Autodesk Fusion 360 part; units mm, degrees
(part 2 of 3)
sketch "24 tooth involute gear profile (2)" plane through (0, 0, 3) normal (0, 0, 1) x (1, 0, 0) in component "Right 24T gear and crank"
  line L0 (25.5783, 0.611) -> (26.1696, 0.6409)
  line L1 (26.1696, 0.6409) -> (26.4898, 0.7065)
  line L2 (26.4898, 0.7065) -> (26.8073, 0.8147)
  line L3 (26.8073, 0.8147) -> (27.1222, 0.9526)
  line L4 (27.1222, 0.9526) -> (27.434, 1.1157)
  line L5 (27.434, 1.1157) -> (27.7424, 1.3018)
  line L6 (27.7424, 1.3018) -> (28.0469, 1.5092)
  line L7 (28.0469, 1.5092) -> (27.9419, 2.3072)
  line L8 (27.9419, 2.3072) -> (27.5941, 2.4288)
  line L9 (27.5941, 2.4288) -> (27.248, 2.5287)
  line L10 (27.248, 2.5287) -> (26.9045, 2.6055)
  line L11 (26.9045, 2.6055) -> (26.5648, 2.6572)
  line L12 (26.5648, 2.6572) -> (26.2301, 2.6796)
  line L13 (26.2301, 2.6796) -> (25.9038, 2.66)
  line L14 (25.9038, 2.66) -> (25.3249, 2.5359)
  line L15 (25.3249, 2.5359) -> (25.0086, 3.7163)
  line L16 (25.0086, 3.7163) -> (25.5721, 3.8982)
  line L17 (25.5721, 3.8982) -> (25.8644, 4.0445)
  line L18 (25.8644, 4.0445) -> (26.143, 4.2312)
  line L19 (26.143, 4.2312) -> (26.4114, 4.4458)
  line L20 (26.4114, 4.4458) -> (26.6705, 4.6841)
  line L21 (26.6705, 4.6841) -> (26.9202, 4.9436)
  line L22 (26.9202, 4.9436) -> (27.1606, 5.2228)
  line L23 (27.1606, 5.2228) -> (26.8526, 5.9664)
  line L24 (26.8526, 5.9664) -> (26.4852, 5.9939)
  line L25 (26.4852, 5.9939) -> (26.1251, 6.0008)
  line L26 (26.1251, 6.0008) -> (25.7734, 5.9861)
  line L27 (25.7734, 5.9861) -> (25.4318, 5.9481)
  line L28 (25.4318, 5.9481) -> (25.1028, 5.8831)
  line L29 (25.1028, 5.8831) -> (24.7927, 5.7798)
  line L30 (24.7927, 5.7798) -> (24.2656, 5.51)
  line L31 (24.2656, 5.51) -> (23.6546, 6.5683)
  line L32 (23.6546, 6.5683) -> (24.1518, 6.8899)
  line L33 (24.1518, 6.8899) -> (24.3963, 7.1068)
  line L34 (24.3963, 7.1068) -> (24.6171, 7.3592)
  line L35 (24.6171, 7.3592) -> (24.8208, 7.636)
  line L36 (24.8208, 7.636) -> (25.0094, 7.9332)
  line L37 (25.0094, 7.9332) -> (25.1834, 8.2486)
  line L38 (25.1834, 8.2486) -> (25.3434, 8.5805)
  line L39 (25.3434, 8.5805) -> (24.8534, 9.219)
  line L40 (24.8534, 9.219) -> (24.4914, 9.1504)
  line L41 (24.4914, 9.1504) -> (24.1418, 9.0639)
  line L42 (24.1418, 9.0639) -> (23.8059, 8.9587)
  line L43 (23.8059, 8.9587) -> (23.4858, 8.8336)
  line L44 (23.4858, 8.8336) -> (23.1848, 8.6856)
  line L45 (23.1848, 8.6856) -> (22.912, 8.5056)
  line L46 (22.912, 8.5056) -> (22.4727, 8.1086)
  line L47 (22.4727, 8.1086) -> (21.6086, 8.9727)
  line L48 (21.6086, 8.9727) -> (22.0056, 9.412)
  line L49 (22.0056, 9.412) -> (22.1856, 9.6848)
  line L50 (22.1856, 9.6848) -> (22.3336, 9.9858)
  line L51 (22.3336, 9.9858) -> (22.4587, 10.3059)
  line L52 (22.4587, 10.3059) -> (22.5639, 10.6418)
  line L53 (22.5639, 10.6418) -> (22.6504, 10.9914)
  line L54 (22.6504, 10.9914) -> (22.719, 11.3534)
  line L55 (22.719, 11.3534) -> (22.0805, 11.8434)
  line L56 (22.0805, 11.8434) -> (21.7486, 11.6834)
  line L57 (21.7486, 11.6834) -> (21.4332, 11.5094)
  line L58 (21.4332, 11.5094) -> (21.136, 11.3208)
  line L59 (21.136, 11.3208) -> (20.8592, 11.1171)
  line L60 (20.8592, 11.1171) -> (20.6068, 10.8963)
  line L61 (20.6068, 10.8963) -> (20.3899, 10.6518)
  line L62 (20.3899, 10.6518) -> (20.0683, 10.1546)
  line L63 (20.0683, 10.1546) -> (19.01, 10.7656)
  line L64 (19.01, 10.7656) -> (19.2798, 11.2927)
  line L65 (19.2798, 11.2927) -> (19.3831, 11.6028)
  line L66 (19.3831, 11.6028) -> (19.4481, 11.9318)
  line L67 (19.4481, 11.9318) -> (19.4861, 12.2734)
  line L68 (19.4861, 12.2734) -> (19.5008, 12.6251)
  line L69 (19.5008, 12.6251) -> (19.4939, 12.9852)
  line L70 (19.4939, 12.9852) -> (19.4664, 13.3526)
  line L71 (19.4664, 13.3526) -> (18.7228, 13.6606)
  line L72 (18.7228, 13.6606) -> (18.4436, 13.4202)
  line L73 (18.4436, 13.4202) -> (18.1841, 13.1705)
  line L74 (18.1841, 13.1705) -> (17.9458, 12.9114)
  line L75 (17.9458, 12.9114) -> (17.7312, 12.643)
  line L76 (17.7312, 12.643) -> (17.5445, 12.3644)
  line L77 (17.5445, 12.3644) -> (17.3982, 12.0721)
  line L78 (17.3982, 12.0721) -> (17.2163, 11.5086)
  line L79 (17.2163, 11.5086) -> (16.0359, 11.8249)
  line L80 (16.0359, 11.8249) -> (16.16, 12.4038)
  line L81 (16.16, 12.4038) -> (16.1796, 12.7301)
  line L82 (16.1796, 12.7301) -> (16.1572, 13.0648)
  line L83 (16.1572, 13.0648) -> (16.1055, 13.4045)
  line L84 (16.1055, 13.4045) -> (16.0287, 13.748)
  line L85 (16.0287, 13.748) -> (15.9288, 14.0941)
  line L86 (15.9288, 14.0941) -> (15.8072, 14.4419)
  line L87 (15.8072, 14.4419) -> (15.0092, 14.5469)
  line L88 (15.0092, 14.5469) -> (14.8018, 14.2424)
  line L89 (14.8018, 14.2424) -> (14.6157, 13.934)
  line L90 (14.6157, 13.934) -> (14.4526, 13.6222)
  line L91 (14.4526, 13.6222) -> (14.3147, 13.3073)
  line L92 (14.3147, 13.3073) -> (14.2065, 12.9898)
  line L93 (14.2065, 12.9898) -> (14.1409, 12.6696)
  line L94 (14.1409, 12.6696) -> (14.111, 12.0783)
  line L95 (14.111, 12.0783) -> (12.889, 12.0783)
  line L96 (12.889, 12.0783) -> (12.8591, 12.6696)
  line L97 (12.8591, 12.6696) -> (12.7935, 12.9898)
  line L98 (12.7935, 12.9898) -> (12.6853, 13.3073)
  line L99 (12.6853, 13.3073) -> (12.5474, 13.6222)
  line L100 (12.5474, 13.6222) -> (12.3843, 13.934)
  line L101 (12.3843, 13.934) -> (12.1982, 14.2424)
  line L102 (12.1982, 14.2424) -> (11.9908, 14.5469)
  line L103 (11.9908, 14.5469) -> (11.1928, 14.4419)
  line L104 (11.1928, 14.4419) -> (11.0712, 14.0941)
  line L105 (11.0712, 14.0941) -> (10.9713, 13.748)
  line L106 (10.9713, 13.748) -> (10.8945, 13.4045)
  line L107 (10.8945, 13.4045) -> (10.8428, 13.0648)
  line L108 (10.8428, 13.0648) -> (10.8204, 12.7301)
  line L109 (10.8204, 12.7301) -> (10.84, 12.4038)
  line L110 (10.84, 12.4038) -> (10.9641, 11.8249)
  line L111 (10.9641, 11.8249) -> (9.7837, 11.5086)
  line L112 (9.7837, 11.5086) -> (9.6018, 12.0721)
  line L113 (9.6018, 12.0721) -> (9.4555, 12.3644)
  line L114 (9.4555, 12.3644) -> (9.2688, 12.643)
  line L115 (9.2688, 12.643) -> (9.0542, 12.9114)
  line L116 (9.0542, 12.9114) -> (8.8159, 13.1705)
  line L117 (8.8159, 13.1705) -> (8.5564, 13.4202)
  line L118 (8.5564, 13.4202) -> (8.2772, 13.6606)
  line L119 (8.2772, 13.6606) -> (7.5336, 13.3526)
  line L120 (7.5336, 13.3526) -> (7.5061, 12.9852)
  line L121 (7.5061, 12.9852) -> (7.4992, 12.6251)
  line L122 (7.4992, 12.6251) -> (7.5139, 12.2734)
  line L123 (7.5139, 12.2734) -> (7.5519, 11.9318)
  line L124 (7.5519, 11.9318) -> (7.6169, 11.6028)
  line L125 (7.6169, 11.6028) -> (7.7202, 11.2927)
  line L126 (7.7202, 11.2927) -> (7.99, 10.7656)
  line L127 (7.99, 10.7656) -> (6.9317, 10.1546)
  line L128 (6.9317, 10.1546) -> (6.6101, 10.6518)
  line L129 (6.6101, 10.6518) -> (6.3932, 10.8963)
  line L130 (6.3932, 10.8963) -> (6.1408, 11.1171)
  line L131 (6.1408, 11.1171) -> (5.864, 11.3208)
  line L132 (5.864, 11.3208) -> (5.5668, 11.5094)
  line L133 (5.5668, 11.5094) -> (5.2514, 11.6834)
  line L134 (5.2514, 11.6834) -> (4.9195, 11.8434)
  line L135 (4.9195, 11.8434) -> (4.281, 11.3534)
  line L136 (4.281, 11.3534) -> (4.3496, 10.9914)
  line L137 (4.3496, 10.9914) -> (4.4361, 10.6418)
  line L138 (4.4361, 10.6418) -> (4.5413, 10.3059)
  line L139 (4.5413, 10.3059) -> (4.6664, 9.9858)
  line L140 (4.6664, 9.9858) -> (4.8144, 9.6848)
  line L141 (4.8144, 9.6848) -> (4.9944, 9.412)
  line L142 (4.9944, 9.412) -> (5.3914, 8.9727)
  line L143 (5.3914, 8.9727) -> (4.5273, 8.1086)
  line L144 (4.5273, 8.1086) -> (4.088, 8.5056)
  line L145 (4.088, 8.5056) -> (3.8152, 8.6856)
  line L146 (3.8152, 8.6856) -> (3.5142, 8.8336)
  line L147 (3.5142, 8.8336) -> (3.1941, 8.9587)
  line L148 (3.1941, 8.9587) -> (2.8582, 9.0639)
  line L149 (2.8582, 9.0639) -> (2.5086, 9.1504)
  line L150 (2.5086, 9.1504) -> (2.1466, 9.219)
  line L151 (2.1466, 9.219) -> (1.6566, 8.5805)
  line L152 (1.6566, 8.5805) -> (1.8166, 8.2486)
  line L153 (1.8166, 8.2486) -> (1.9906, 7.9332)
  line L154 (1.9906, 7.9332) -> (2.1792, 7.636)
  line L155 (2.1792, 7.636) -> (2.3829, 7.3592)
  line L156 (2.3829, 7.3592) -> (2.6037, 7.1068)
  line L157 (2.6037, 7.1068) -> (2.8482, 6.8899)
  line L158 (2.8482, 6.8899) -> (3.3454, 6.5683)
  line L159 (3.3454, 6.5683) -> (2.7344, 5.51)
  line L160 (2.7344, 5.51) -> (2.2073, 5.7798)
  line L161 (2.2073, 5.7798) -> (1.8972, 5.8831)
  line L162 (1.8972, 5.8831) -> (1.5682, 5.9481)
  line L163 (1.5682, 5.9481) -> (1.2266, 5.9861)
  line L164 (1.2266, 5.9861) -> (0.8749, 6.0008)
  line L165 (0.8749, 6.0008) -> (0.5148, 5.9939)
  line L166 (0.5148, 5.9939) -> (0.1474, 5.9664)
  line L167 (0.1474, 5.9664) -> (-0.1606, 5.2228)
  line L168 (-0.1606, 5.2228) -> (0.0798, 4.9436)
  line L169 (0.0798, 4.9436) -> (0.3295, 4.6841)
  line L170 (0.3295, 4.6841) -> (0.5886, 4.4458)
  line L171 (0.5886, 4.4458) -> (0.857, 4.2312)
  line L172 (0.857, 4.2312) -> (1.1356, 4.0445)
  line L173 (1.1356, 4.0445) -> (1.4279, 3.8982)
  line L174 (1.4279, 3.8982) -> (1.9914, 3.7163)
  line L175 (1.9914, 3.7163) -> (1.6751, 2.5359)
  line L176 (1.6751, 2.5359) -> (1.0962, 2.66)
  line L177 (1.0962, 2.66) -> (0.7699, 2.6796)
  line L178 (0.7699, 2.6796) -> (0.4352, 2.6572)
  line L179 (0.4352, 2.6572) -> (0.0955, 2.6055)
  line L180 (0.0955, 2.6055) -> (-0.248, 2.5287)
  line L181 (-0.248, 2.5287) -> (-0.5941, 2.4288)
  line L182 (-0.5941, 2.4288) -> (-0.9419, 2.3072)
  line L183 (-0.9419, 2.3072) -> (-1.0469, 1.5092)
  line L184 (-1.0469, 1.5092) -> (-0.7424, 1.3018)
  line L185 (-0.7424, 1.3018) -> (-0.434, 1.1157)
  line L186 (-0.434, 1.1157) -> (-0.1222, 0.9526)
  line L187 (-0.1222, 0.9526) -> (0.1927, 0.8147)
  line L188 (0.1927, 0.8147) -> (0.5102, 0.7065)
  line L189 (0.5102, 0.7065) -> (0.8304, 0.6409)
  line L190 (0.8304, 0.6409) -> (1.4217, 0.611)
  line L191 (1.4217, 0.611) -> (1.4217, -0.611)
  line L192 (1.4217, -0.611) -> (0.8304, -0.6409)
  line L193 (0.8304, -0.6409) -> (0.5102, -0.7065)
  line L194 (0.5102, -0.7065) -> (0.1927, -0.8147)
  line L195 (0.1927, -0.8147) -> (-0.1222, -0.9526)
  line L196 (-0.1222, -0.9526) -> (-0.434, -1.1157)
  line L197 (-0.434, -1.1157) -> (-0.7424, -1.3018)
  line L198 (-0.7424, -1.3018) -> (-1.0469, -1.5092)
  line L199 (-1.0469, -1.5092) -> (-0.9419, -2.3072)
  line L200 (-0.9419, -2.3072) -> (-0.5941, -2.4288)
  line L201 (-0.5941, -2.4288) -> (-0.248, -2.5287)
  line L202 (-0.248, -2.5287) -> (0.0955, -2.6055)
  line L203 (0.0955, -2.6055) -> (0.4352, -2.6572)
  line L204 (0.4352, -2.6572) -> (0.7699, -2.6796)
  line L205 (0.7699, -2.6796) -> (1.0962, -2.66)
  line L206 (1.0962, -2.66) -> (1.6751, -2.5359)
  line L207 (1.6751, -2.5359) -> (1.9914, -3.7163)
  line L208 (1.9914, -3.7163) -> (1.4279, -3.8982)
  line L209 (1.4279, -3.8982) -> (1.1356, -4.0445)
  line L210 (1.1356, -4.0445) -> (0.857, -4.2312)
  line L211 (0.857, -4.2312) -> (0.5886, -4.4458)
  line L212 (0.5886, -4.4458) -> (0.3295, -4.6841)
  line L213 (0.3295, -4.6841) -> (0.0798, -4.9436)
  line L214 (0.0798, -4.9436) -> (-0.1606, -5.2228)
  line L215 (-0.1606, -5.2228) -> (0.1474, -5.9664)
  line L216 (0.1474, -5.9664) -> (0.5148, -5.9939)
  line L217 (0.5148, -5.9939) -> (0.8749, -6.0008)
  line L218 (0.8749, -6.0008) -> (1.2266, -5.9861)
  line L219 (1.2266, -5.9861) -> (1.5682, -5.9481)
  line L220 (1.5682, -5.9481) -> (1.8972, -5.8831)
  line L221 (1.8972, -5.8831) -> (2.2073, -5.7798)
  line L222 (2.2073, -5.7798) -> (2.7344, -5.51)
  line L223 (2.7344, -5.51) -> (3.3454, -6.5683)
  line L224 (3.3454, -6.5683) -> (2.8482, -6.8899)
  line L225 (2.8482, -6.8899) -> (2.6037, -7.1068)
  line L226 (2.6037, -7.1068) -> (2.3829, -7.3592)
  line L227 (2.3829, -7.3592) -> (2.1792, -7.636)
  line L228 (2.1792, -7.636) -> (1.9906, -7.9332)
  line L229 (1.9906, -7.9332) -> (1.8166, -8.2486)
  line L230 (1.8166, -8.2486) -> (1.6566, -8.5805)
  line L231 (1.6566, -8.5805) -> (2.1466, -9.219)
  line L232 (2.1466, -9.219) -> (2.5086, -9.1504)
  line L233 (2.5086, -9.1504) -> (2.8582, -9.0639)
  line L234 (2.8582, -9.0639) -> (3.1941, -8.9587)
  line L235 (3.1941, -8.9587) -> (3.5142, -8.8336)
  line L236 (3.5142, -8.8336) -> (3.8152, -8.6856)
  line L237 (3.8152, -8.6856) -> (4.088, -8.5056)
  line L238 (4.088, -8.5056) -> (4.5273, -8.1086)
  line L239 (4.5273, -8.1086) -> (5.3914, -8.9727)
  line L240 (5.3914, -8.9727) -> (4.9944, -9.412)
  line L241 (4.9944, -9.412) -> (4.8144, -9.6848)
  line L242 (4.8144, -9.6848) -> (4.6664, -9.9858)
  line L243 (4.6664, -9.9858) -> (4.5413, -10.3059)
  line L244 (4.5413, -10.3059) -> (4.4361, -10.6418)
  line L245 (4.4361, -10.6418) -> (4.3496, -10.9914)
  line L246 (4.3496, -10.9914) -> (4.281, -11.3534)
  line L247 (4.281, -11.3534) -> (4.9195, -11.8434)
  line L248 (4.9195, -11.8434) -> (5.2514, -11.6834)
  line L249 (5.2514, -11.6834) -> (5.5668, -11.5094)
  line L250 (5.5668, -11.5094) -> (5.864, -11.3208)
  line L251 (5.864, -11.3208) -> (6.1408, -11.1171)
  line L252 (6.1408, -11.1171) -> (6.3932, -10.8963)
  line L253 (6.3932, -10.8963) -> (6.6101, -10.6518)
  line L254 (6.6101, -10.6518) -> (6.9317, -10.1546)
  line L255 (6.9317, -10.1546) -> (7.99, -10.7656)
  line L256 (7.99, -10.7656) -> (7.7202, -11.2927)
  line L257 (7.7202, -11.2927) -> (7.6169, -11.6028)
  line L258 (7.6169, -11.6028) -> (7.5519, -11.9318)
  line L259 (7.5519, -11.9318) -> (7.5139, -12.2734)
  line L260 (7.5139, -12.2734) -> (7.4992, -12.6251)
  line L261 (7.4992, -12.6251) -> (7.5061, -12.9852)
  line L262 (7.5061, -12.9852) -> (7.5336, -13.3526)
  line L263 (7.5336, -13.3526) -> (8.2772, -13.6606)
  line L264 (8.2772, -13.6606) -> (8.5564, -13.4202)
  line L265 (8.5564, -13.4202) -> (8.8159, -13.1705)
  line L266 (8.8159, -13.1705) -> (9.0542, -12.9114)
  line L267 (9.0542, -12.9114) -> (9.2688, -12.643)
  line L268 (9.2688, -12.643) -> (9.4555, -12.3644)
  line L269 (9.4555, -12.3644) -> (9.6018, -12.0721)
  line L270 (9.6018, -12.0721) -> (9.7837, -11.5086)
  line L271 (9.7837, -11.5086) -> (10.9641, -11.8249)
  line L272 (10.9641, -11.8249) -> (10.84, -12.4038)
  line L273 (10.84, -12.4038) -> (10.8204, -12.7301)
  line L274 (10.8204, -12.7301) -> (10.8428, -13.0648)
  line L275 (10.8428, -13.0648) -> (10.8945, -13.4045)
  line L276 (10.8945, -13.4045) -> (10.9713, -13.748)
  line L277 (10.9713, -13.748) -> (11.0712, -14.0941)
  line L278 (11.0712, -14.0941) -> (11.1928, -14.4419)
  line L279 (11.1928, -14.4419) -> (11.9908, -14.5469)
  line L280 (11.9908, -14.5469) -> (12.1982, -14.2424)
  line L281 (12.1982, -14.2424) -> (12.3843, -13.934)
  line L282 (12.3843, -13.934) -> (12.5474, -13.6222)
  line L283 (12.5474, -13.6222) -> (12.6853, -13.3073)
  line L284 (12.6853, -13.3073) -> (12.7935, -12.9898)
  line L285 (12.7935, -12.9898) -> (12.8591, -12.6696)
  line L286 (12.8591, -12.6696) -> (12.889, -12.0783)
  line L287 (12.889, -12.0783) -> (14.111, -12.0783)
  line L288 (14.111, -12.0783) -> (14.1409, -12.6696)
  line L289 (14.1409, -12.6696) -> (14.2065, -12.9898)
  line L290 (14.2065, -12.9898) -> (14.3147, -13.3073)
  line L291 (14.3147, -13.3073) -> (14.4526, -13.6222)
  line L292 (14.4526, -13.6222) -> (14.6157, -13.934)
  line L293 (14.6157, -13.934) -> (14.8018, -14.2424)
  line L294 (14.8018, -14.2424) -> (15.0092, -14.5469)
  line L295 (15.0092, -14.5469) -> (15.8072, -14.4419)
  line L296 (15.8072, -14.4419) -> (15.9288, -14.0941)
  line L297 (15.9288, -14.0941) -> (16.0287, -13.748)
  line L298 (16.0287, -13.748) -> (16.1055, -13.4045)
  line L299 (16.1055, -13.4045) -> (16.1572, -13.0648)
  line L300 (16.1572, -13.0648) -> (16.1796, -12.7301)
  line L301 (16.1796, -12.7301) -> (16.16, -12.4038)
  line L302 (16.16, -12.4038) -> (16.0359, -11.8249)
  line L303 (16.0359, -11.8249) -> (17.2163, -11.5086)
  line L304 (17.2163, -11.5086) -> (17.3982, -12.0721)
  line L305 (17.3982, -12.0721) -> (17.5445, -12.3644)
  line L306 (17.5445, -12.3644) -> (17.7312, -12.643)
  line L307 (17.7312, -12.643) -> (17.9458, -12.9114)
  line L308 (17.9458, -12.9114) -> (18.1841, -13.1705)
  line L309 (18.1841, -13.1705) -> (18.4436, -13.4202)
  line L310 (18.4436, -13.4202) -> (18.7228, -13.6606)
  line L311 (18.7228, -13.6606) -> (19.4664, -13.3526)
  line L312 (19.4664, -13.3526) -> (19.4939, -12.9852)
  line L313 (19.4939, -12.9852) -> (19.5008, -12.6251)
  line L314 (19.5008, -12.6251) -> (19.4861, -12.2734)
  line L315 (19.4861, -12.2734) -> (19.4481, -11.9318)
  line L316 (19.4481, -11.9318) -> (19.3831, -11.6028)
  line L317 (19.3831, -11.6028) -> (19.2798, -11.2927)
  line L318 (19.2798, -11.2927) -> (19.01, -10.7656)
  line L319 (19.01, -10.7656) -> (20.0683, -10.1546)
  line L320 (20.0683, -10.1546) -> (20.3899, -10.6518)
  line L321 (20.3899, -10.6518) -> (20.6068, -10.8963)
  line L322 (20.6068, -10.8963) -> (20.8592, -11.1171)
  line L323 (20.8592, -11.1171) -> (21.136, -11.3208)
  line L324 (21.136, -11.3208) -> (21.4332, -11.5094)
  line L325 (21.4332, -11.5094) -> (21.7486, -11.6834)
  line L326 (21.7486, -11.6834) -> (22.0805, -11.8434)
  line L327 (22.0805, -11.8434) -> (22.719, -11.3534)
  line L328 (22.719, -11.3534) -> (22.6504, -10.9914)
  line L329 (22.6504, -10.9914) -> (22.5639, -10.6418)
  line L330 (22.5639, -10.6418) -> (22.4587, -10.3059)
  line L331 (22.4587, -10.3059) -> (22.3336, -9.9858)
  line L332 (22.3336, -9.9858) -> (22.1856, -9.6848)
  line L333 (22.1856, -9.6848) -> (22.0056, -9.412)
  line L334 (22.0056, -9.412) -> (21.6086, -8.9727)
  line L335 (21.6086, -8.9727) -> (22.4727, -8.1086)
  line L336 (22.4727, -8.1086) -> (22.912, -8.5056)
  line L337 (22.912, -8.5056) -> (23.1848, -8.6856)
  line L338 (23.1848, -8.6856) -> (23.4858, -8.8336)
  line L339 (23.4858, -8.8336) -> (23.8059, -8.9587)
  line L340 (23.8059, -8.9587) -> (24.1418, -9.0639)
  line L341 (24.1418, -9.0639) -> (24.4914, -9.1504)
  line L342 (24.4914, -9.1504) -> (24.8534, -9.219)
  line L343 (24.8534, -9.219) -> (25.3434, -8.5805)
  line L344 (25.3434, -8.5805) -> (25.1834, -8.2486)
  line L345 (25.1834, -8.2486) -> (25.0094, -7.9332)
  line L346 (25.0094, -7.9332) -> (24.8208, -7.636)
  line L347 (24.8208, -7.636) -> (24.6171, -7.3592)
  line L348 (24.6171, -7.3592) -> (24.3963, -7.1068)
  line L349 (24.3963, -7.1068) -> (24.1518, -6.8899)
  line L350 (24.1518, -6.8899) -> (23.6546, -6.5683)
  line L351 (23.6546, -6.5683) -> (24.2656, -5.51)
  line L352 (24.2656, -5.51) -> (24.7927, -5.7798)
  line L353 (24.7927, -5.7798) -> (25.1028, -5.8831)
  line L354 (25.1028, -5.8831) -> (25.4318, -5.9481)
  line L355 (25.4318, -5.9481) -> (25.7734, -5.9861)
  line L356 (25.7734, -5.9861) -> (26.1251, -6.0008)
  line L357 (26.1251, -6.0008) -> (26.4852, -5.9939)
  line L358 (26.4852, -5.9939) -> (26.8526, -5.9664)
  line L359 (26.8526, -5.9664) -> (27.1606, -5.2228)
  line L360 (27.1606, -5.2228) -> (26.9202, -4.9436)
  line L361 (26.9202, -4.9436) -> (26.6705, -4.6841)
  line L362 (26.6705, -4.6841) -> (26.4114, -4.4458)
  line L363 (26.4114, -4.4458) -> (26.143, -4.2312)
  line L364 (26.143, -4.2312) -> (25.8644, -4.0445)
  line L365 (25.8644, -4.0445) -> (25.5721, -3.8982)
  line L366 (25.5721, -3.8982) -> (25.0086, -3.7163)
  line L367 (25.0086, -3.7163) -> (25.3249, -2.5359)
  line L368 (25.3249, -2.5359) -> (25.9038, -2.66)
  line L369 (25.9038, -2.66) -> (26.2301, -2.6796)
  line L370 (26.2301, -2.6796) -> (26.5648, -2.6572)
  line L371 (26.5648, -2.6572) -> (26.9045, -2.6055)
  line L372 (26.9045, -2.6055) -> (27.248, -2.5287)
  line L373 (27.248, -2.5287) -> (27.5941, -2.4288)
  line L374 (27.5941, -2.4288) -> (27.9419, -2.3072)
  line L375 (27.9419, -2.3072) -> (28.0469, -1.5092)
  line L376 (28.0469, -1.5092) -> (27.7424, -1.3018)
  line L377 (27.7424, -1.3018) -> (27.434, -1.1157)
  line L378 (27.434, -1.1157) -> (27.1222, -0.9526)
  line L379 (27.1222, -0.9526) -> (26.8073, -0.8147)
  line L380 (26.8073, -0.8147) -> (26.4898, -0.7065)
  line L381 (26.4898, -0.7065) -> (26.1696, -0.6409)
  line L382 (26.1696, -0.6409) -> (25.5783, -0.611)
  line L383 (25.5783, -0.611) -> (25.5783, 0.611)
extrude "24 tooth involute gear'" add sketch "24 tooth involute gear profile (2)" along normal blind 3 separate body makes body 22 in component "Right 24T gear and crank"
ref_plane "WorkPlane2" through (0, 0, 3) normal (0, 0, 1) x (1, 0, 0) in component "Right 24T gear and crank"
sketch "31 mm crank profile (2)" plane through (0, 0, 3) normal (0, 0, 1) x (1, 0, 0) in component "Right 24T gear and crank"
  line L0 (30.2264, 26.4051) -> (30.5404, 27.4009)
  line L1 (30.5404, 27.4009) -> (30.5859, 28.4442)
  line L2 (30.5859, 28.4442) -> (30.3599, 29.4636)
  line L3 (30.3599, 29.4636) -> (29.8778, 30.3898)
  line L4 (29.8778, 30.3898) -> (29.1723, 31.1597)
  line L5 (29.1723, 31.1597) -> (28.2916, 31.7208)
  line L6 (28.2916, 31.7208) -> (27.2958, 32.0348)
  line L7 (27.2958, 32.0348) -> (26.2525, 32.0803)
  line L8 (26.2525, 32.0803) -> (25.2331, 31.8543)
  line L9 (25.2331, 31.8543) -> (24.3069, 31.3721)
  line L10 (24.3069, 31.3721) -> (23.537, 30.6667)
  line L11 (23.537, 30.6667) -> (22.9759, 29.786)
  line L12 (22.9759, 29.786) -> (9.8748, 1.6905)
  line L13 (9.8748, 1.6905) -> (9.5608, 0.6946)
  line L14 (9.5608, 0.6946) -> (9.5152, -0.3486)
  line L15 (9.5152, -0.3486) -> (9.7412, -1.3681)
  line L16 (9.7412, -1.3681) -> (10.2234, -2.2943)
  line L17 (10.2234, -2.2943) -> (10.9288, -3.0642)
  line L18 (10.9288, -3.0642) -> (11.8095, -3.6252)
  line L19 (11.8095, -3.6252) -> (12.8054, -3.9392)
  line L20 (12.8054, -3.9392) -> (13.8486, -3.9848)
  line L21 (13.8486, -3.9848) -> (14.8681, -3.7588)
  line L22 (14.8681, -3.7588) -> (15.7943, -3.2766)
  line L23 (15.7943, -3.2766) -> (16.5642, -2.5712)
  line L24 (16.5642, -2.5712) -> (17.1252, -1.6905)
  line L25 (17.1252, -1.6905) -> (30.2264, 26.4051)
extrude "31 mm crank'" add sketch "31 mm crank profile (2)" along normal blind 3 separate body makes body 23 in component "Right 24T gear and crank"
ref_plane "WorkPlane3" through (0, 0, 3) normal (0, 0, 1) x (1, 0, 0) in component "Right 24T gear and crank"
sketch "Pivot holes (6)" plane through (0, 0, 3) normal (0, 0, 1) x (1, 0, 0) in component "Right 24T gear and crank"
  circle A0 centre (13.5, 0) radius 1.5
  circle A1 centre (26.6012, 28.0955) radius 1.5
extrude "Through holes'''''" cut sketch "Pivot holes (6)" along normal blind 3 bodies 22 23 in component "Right 24T gear and crank"
sketch "Right gear pivot axis" plane through (0, 0, 0) normal (0, 0, 1) x (1, 0, 0) in component "Frame - twin 3 mm plates"
  point P0 (13.5, 0)
ref_plane "WorkPlane1" through (0, 0, 3) normal (0, 0, 1) x (1, 0, 0) in component "Right parallel links"
sketch "31 mm parallel link profile (2)" plane through (0, 0, 3) normal (0, 0, 1) x (1, 0, 0) in component "Right parallel links"
  line L0 (29.7732, 48.6164) -> (30.048, 49.4878)
  line L1 (30.048, 49.4878) -> (30.0878, 50.4006)
  line L2 (30.0878, 50.4006) -> (29.8901, 51.2926)
  line L3 (29.8901, 51.2926) -> (29.4682, 52.1031)
  line L4 (29.4682, 52.1031) -> (28.8509, 52.7767)
  line L5 (28.8509, 52.7767) -> (28.0803, 53.2676)
  line L6 (28.0803, 53.2676) -> (27.2089, 53.5424)
  line L7 (27.2089, 53.5424) -> (26.2961, 53.5822)
  line L8 (26.2961, 53.5822) -> (25.4041, 53.3845)
  line L9 (25.4041, 53.3845) -> (24.5936, 52.9626)
  line L10 (24.5936, 52.9626) -> (23.92, 52.3453)
  line L11 (23.92, 52.3453) -> (23.4291, 51.5747)
  line L12 (23.4291, 51.5747) -> (10.3279, 23.4792)
  line L13 (10.3279, 23.4792) -> (10.0532, 22.6078)
  line L14 (10.0532, 22.6078) -> (10.0133, 21.695)
  line L15 (10.0133, 21.695) -> (10.2111, 20.8029)
  line L16 (10.2111, 20.8029) -> (10.633, 19.9925)
  line L17 (10.633, 19.9925) -> (11.2502, 19.3188)
  line L18 (11.2502, 19.3188) -> (12.0208, 18.8279)
  line L19 (12.0208, 18.8279) -> (12.8922, 18.5532)
  line L20 (12.8922, 18.5532) -> (13.805, 18.5133)
  line L21 (13.805, 18.5133) -> (14.6971, 18.7111)
  line L22 (14.6971, 18.7111) -> (15.5075, 19.133)
  line L23 (15.5075, 19.133) -> (16.1812, 19.7502)
  line L24 (16.1812, 19.7502) -> (16.6721, 20.5208)
  line L25 (16.6721, 20.5208) -> (29.7732, 48.6164)
extrude "31 mm parallel link'" add sketch "31 mm parallel link profile (2)" along normal blind 3 separate body makes body 24 in component "Right parallel links"
ref_plane "WorkPlane2" through (0, 0, 3) normal (0, 0, 1) x (1, 0, 0) in component "Right parallel links"
sketch "Pivot holes (7)" plane through (0, 0, 3) normal (0, 0, 1) x (1, 0, 0) in component "Right parallel links"
  circle A0 centre (13.5, 22) radius 1.5
  circle A1 centre (26.6012, 50.0955) radius 1.5
extrude "Through holes''''''" cut sketch "Pivot holes (7)" along normal blind 3 bodies 24 in component "Right parallel links"
ref_plane "WorkPlane3" through (0, 0, -6) normal (0, 0, 1) x (1, 0, 0) in component "Right parallel links"
sketch "31 mm parallel link profile (1) (2)" plane through (0, 0, -6) normal (0, 0, 1) x (1, 0, 0) in component "Right parallel links"
  line L0 (29.7732, 48.6164) -> (30.048, 49.4878)
  line L1 (30.048, 49.4878) -> (30.0878, 50.4006)
  line L2 (30.0878, 50.4006) -> (29.8901, 51.2926)
  line L3 (29.8901, 51.2926) -> (29.4682, 52.1031)
  line L4 (29.4682, 52.1031) -> (28.8509, 52.7767)
  line L5 (28.8509, 52.7767) -> (28.0803, 53.2676)
  line L6 (28.0803, 53.2676) -> (27.2089, 53.5424)
  line L7 (27.2089, 53.5424) -> (26.2961, 53.5822)
  line L8 (26.2961, 53.5822) -> (25.4041, 53.3845)
  line L9 (25.4041, 53.3845) -> (24.5936, 52.9626)
  line L10 (24.5936, 52.9626) -> (23.92, 52.3453)
  line L11 (23.92, 52.3453) -> (23.4291, 51.5747)
  line L12 (23.4291, 51.5747) -> (10.3279, 23.4792)
  line L13 (10.3279, 23.4792) -> (10.0532, 22.6078)
  line L14 (10.0532, 22.6078) -> (10.0133, 21.695)
  line L15 (10.0133, 21.695) -> (10.2111, 20.8029)
  line L16 (10.2111, 20.8029) -> (10.633, 19.9925)
  line L17 (10.633, 19.9925) -> (11.2502, 19.3188)
  line L18 (11.2502, 19.3188) -> (12.0208, 18.8279)
  line L19 (12.0208, 18.8279) -> (12.8922, 18.5532)
  line L20 (12.8922, 18.5532) -> (13.805, 18.5133)
  line L21 (13.805, 18.5133) -> (14.6971, 18.7111)
  line L22 (14.6971, 18.7111) -> (15.5075, 19.133)
  line L23 (15.5075, 19.133) -> (16.1812, 19.7502)
  line L24 (16.1812, 19.7502) -> (16.6721, 20.5208)
  line L25 (16.6721, 20.5208) -> (29.7732, 48.6164)
extrude "31 mm parallel link (1)'" add sketch "31 mm parallel link profile (1) (2)" along normal blind 3 separate body makes body 25 in component "Right parallel links"
ref_plane "WorkPlane4" through (0, 0, -6) normal (0, 0, 1) x (1, 0, 0) in component "Right parallel links"
sketch "Pivot holes (1) (3)" plane through (0, 0, -6) normal (0, 0, 1) x (1, 0, 0) in component "Right parallel links"
  circle A0 centre (13.5, 22) radius 1.5
  circle A1 centre (26.6012, 50.0955) radius 1.5
extrude "Through holes (1)''" cut sketch "Pivot holes (1) (3)" along normal blind 3 bodies 25 in component "Right parallel links"
sketch "Right link pivot axis" plane through (0, 0, 0) normal (0, 0, 1) x (1, 0, 0) in component "Frame - twin 3 mm plates"
  point P0 (13.5, 22)
ref_plane "WorkPlane1" through (0, 0, -3) normal (0, 0, 1) x (1, 0, 0) in component "Right jaw - twin plates"
sketch "Jaw plate profile (2)" plane through (0, 0, -3) normal (0, 0, 1) x (1, 0, 0) in component "Right jaw - twin plates"
  line L0 (21.6012, 25.0955) -> (31.6012, 25.0955)
  line L1 (31.6012, 25.0955) -> (31.6012, 53.0955)
  line L2 (31.6012, 53.0955) -> (12, 85.0955)
  line L3 (12, 85.0955) -> (3, 85.0955)
  line L4 (3, 85.0955) -> (3, 77.0955)
  line L5 (3, 77.0955) -> (11, 75.0955)
  line L6 (11, 75.0955) -> (21.6012, 49.0955)
  line L7 (21.6012, 49.0955) -> (21.6012, 25.0955)
extrude "Jaw plate'" add sketch "Jaw plate profile (2)" along normal blind 3 separate body makes body 26 in component "Right jaw - twin plates"
ref_plane "WorkPlane2" through (0, 0, -3) normal (0, 0, 1) x (1, 0, 0) in component "Right jaw - twin plates"
sketch "Pivot holes (8)" plane through (0, 0, -3) normal (0, 0, 1) x (1, 0, 0) in component "Right jaw - twin plates"
  circle A0 centre (26.6012, 28.0955) radius 1.5
  circle A1 centre (26.6012, 50.0955) radius 1.5
extrude "Through holes'''''''" cut sketch "Pivot holes (8)" along normal blind 3 bodies 26 in component "Right jaw - twin plates"
sketch "Jaw plate profile (1) (2)" plane through (0, 0, 0) normal (0, 0, 1) x (1, 0, 0) in component "Right jaw - twin plates"
  line L0 (21.6012, 25.0955) -> (31.6012, 25.0955)
  line L1 (31.6012, 25.0955) -> (31.6012, 53.0955)
  line L2 (31.6012, 53.0955) -> (12, 85.0955)
  line L3 (12, 85.0955) -> (3, 85.0955)
  line L4 (3, 85.0955) -> (3, 77.0955)
  line L5 (3, 77.0955) -> (11, 75.0955)
  line L6 (11, 75.0955) -> (21.6012, 49.0955)
  line L7 (21.6012, 49.0955) -> (21.6012, 25.0955)
extrude "Jaw plate (1)'" add sketch "Jaw plate profile (1) (2)" along normal blind 3 separate body makes body 27 in component "Right jaw - twin plates"
sketch "Pivot holes (1) (4)" plane through (0, 0, 0) normal (0, 0, 1) x (1, 0, 0) in component "Right jaw - twin plates"
  circle A0 centre (26.6012, 28.0955) radius 1.5
  circle A1 centre (26.6012, 50.0955) radius 1.5
extrude "Through holes (1)'''" cut sketch "Pivot holes (1) (4)" along normal blind 3 bodies 27 in component "Right jaw - twin plates"
sketch "Right crank to jaw axis" plane through (0, 0, 0) normal (0, 0, 1) x (1, 0, 0) in component "Right 24T gear and crank"
  point P0 (26.6012, 28.0955)
sketch "Right follower to jaw axis" plane through (0, 0, 0) normal (0, 0, 1) x (1, 0, 0) in component "Right parallel links"
  point P0 (26.6012, 50.0955)
ref_plane "WorkPlane1" through (0, 0, -6) normal (0, 0, 1) x (1, 0, 0) in component "Right lower crank"
sketch "Lower support link profile (2)" plane through (0, 0, -6) normal (0, 0, 1) x (1, 0, 0) in component "Right lower crank"
  line L0 (29.7732, 26.6164) -> (30.048, 27.4878)
  line L1 (30.048, 27.4878) -> (30.0878, 28.4006)
  line L2 (30.0878, 28.4006) -> (29.8901, 29.2926)
  line L3 (29.8901, 29.2926) -> (29.4682, 30.1031)
  line L4 (29.4682, 30.1031) -> (28.8509, 30.7767)
  line L5 (28.8509, 30.7767) -> (28.0803, 31.2676)
  line L6 (28.0803, 31.2676) -> (27.2089, 31.5424)
  line L7 (27.2089, 31.5424) -> (26.2961, 31.5822)
  line L8 (26.2961, 31.5822) -> (25.4041, 31.3845)
  line L9 (25.4041, 31.3845) -> (24.5936, 30.9626)
  line L10 (24.5936, 30.9626) -> (23.92, 30.3453)
  line L11 (23.92, 30.3453) -> (23.4291, 29.5747)
  line L12 (23.4291, 29.5747) -> (10.3279, 1.4792)
  line L13 (10.3279, 1.4792) -> (10.0532, 0.6078)
  line L14 (10.0532, 0.6078) -> (10.0133, -0.305)
  line L15 (10.0133, -0.305) -> (10.2111, -1.1971)
  line L16 (10.2111, -1.1971) -> (10.633, -2.0075)
  line L17 (10.633, -2.0075) -> (11.2502, -2.6812)
  line L18 (11.2502, -2.6812) -> (12.0208, -3.1721)
  line L19 (12.0208, -3.1721) -> (12.8922, -3.4468)
  line L20 (12.8922, -3.4468) -> (13.805, -3.4867)
  line L21 (13.805, -3.4867) -> (14.6971, -3.2889)
  line L22 (14.6971, -3.2889) -> (15.5075, -2.867)
  line L23 (15.5075, -2.867) -> (16.1812, -2.2498)
  line L24 (16.1812, -2.2498) -> (16.6721, -1.4792)
  line L25 (16.6721, -1.4792) -> (29.7732, 26.6164)
extrude "Lower support link'" add sketch "Lower support link profile (2)" along normal blind 3 separate body makes body 28 in component "Right lower crank"
ref_plane "WorkPlane2" through (0, 0, -6) normal (0, 0, 1) x (1, 0, 0) in component "Right lower crank"
sketch "Pivot holes (9)" plane through (0, 0, -6) normal (0, 0, 1) x (1, 0, 0) in component "Right lower crank"
  circle A0 centre (13.5, 0) radius 1.5
  circle A1 centre (26.6012, 28.0955) radius 1.5
extrude "Through holes''''''''" cut sketch "Pivot holes (9)" along normal blind 3 bodies 28 in component "Right lower crank"
ref_plane "WorkPlane1" through (0, 0, -6) normal (0, 0, 1) x (1, 0, 0) in component "Right pivot pin 1"
sketch "Pivot shaft profile (5)" plane through (0, 0, -6) normal (0, 0, 1) x (1, 0, 0) in component "Right pivot pin 1"
  circle A0 centre (13.5, 0) radius 1.5
extrude "Pivot shaft''''" add sketch "Pivot shaft profile (5)" along normal blind 12 separate body makes body 29 in component "Right pivot pin 1"
ref_plane "WorkPlane2" through (0, 0, 6) normal (0, 0, 1) x (1, 0, 0) in component "Right pivot pin 1"
sketch "Pin head profile (5)" plane through (0, 0, 6) normal (0, 0, 1) x (1, 0, 0) in component "Right pivot pin 1"
  circle A0 centre (13.5, 0) radius 2.5
extrude "Pin head''''" add sketch "Pin head profile (5)" along normal blind 1 separate body makes body 30 in component "Right pivot pin 1"
ref_plane "WorkPlane3" through (0, 0, -7) normal (0, 0, 1) x (1, 0, 0) in component "Right pivot pin 1"
sketch "Pin retainer profile (5)" plane through (0, 0, -7) normal (0, 0, 1) x (1, 0, 0) in component "Right pivot pin 1"
  circle A0 centre (13.5, 0) radius 2.5
extrude "Pin retainer''''" add sketch "Pin retainer profile (5)" along normal blind 1 separate body makes body 31 in component "Right pivot pin 1"
ref_plane "WorkPlane1" through (0, 0, -6) normal (0, 0, 1) x (1, 0, 0) in component "Right pivot pin 2"
sketch "Pivot shaft profile (6)" plane through (0, 0, -6) normal (0, 0, 1) x (1, 0, 0) in component "Right pivot pin 2"
  circle A0 centre (13.5, 22) radius 1.5
extrude "Pivot shaft'''''" add sketch "Pivot shaft profile (6)" along normal blind 12 separate body makes body 32 in component "Right pivot pin 2"
ref_plane "WorkPlane2" through (0, 0, 6) normal (0, 0, 1) x (1, 0, 0) in component "Right pivot pin 2"
sketch "Pin head profile (6)" plane through (0, 0, 6) normal (0, 0, 1) x (1, 0, 0) in component "Right pivot pin 2"
  circle A0 centre (13.5, 22) radius 2.5
extrude "Pin head'''''" add sketch "Pin head profile (6)" along normal blind 1 separate body makes body 33 in component "Right pivot pin 2"
ref_plane "WorkPlane3" through (0, 0, -7) normal (0, 0, 1) x (1, 0, 0) in component "Right pivot pin 2"
sketch "Pin retainer profile (6)" plane through (0, 0, -7) normal (0, 0, 1) x (1, 0, 0) in component "Right pivot pin 2"
  circle A0 centre (13.5, 22) radius 2.5
extrude "Pin retainer'''''" add sketch "Pin retainer profile (6)" along normal blind 1 separate body makes body 34 in component "Right pivot pin 2"
ref_plane "WorkPlane1" through (0, 0, -6) normal (0, 0, 1) x (1, 0, 0) in component "Right pivot pin 3"
sketch "Pivot shaft profile (7)" plane through (0, 0, -6) normal (0, 0, 1) x (1, 0, 0) in component "Right pivot pin 3"
  circle A0 centre (26.6012, 28.0955) radius 1.5
extrude "Pivot shaft''''''" add sketch "Pivot shaft profile (7)" along normal blind 12 separate body makes body 35 in component "Right pivot pin 3"
ref_plane "WorkPlane2" through (0, 0, 6) normal (0, 0, 1) x (1, 0, 0) in component "Right pivot pin 3"
sketch "Pin head profile (7)" plane through (0, 0, 6) normal (0, 0, 1) x (1, 0, 0) in component "Right pivot pin 3"
  circle A0 centre (26.6012, 28.0955) radius 2.5
extrude "Pin head''''''" add sketch "Pin head profile (7)" along normal blind 1 separate body makes body 36 in component "Right pivot pin 3"
ref_plane "WorkPlane3" through (0, 0, -7) normal (0, 0, 1) x (1, 0, 0) in component "Right pivot pin 3"
sketch "Pin retainer profile (7)" plane through (0, 0, -7) normal (0, 0, 1) x (1, 0, 0) in component "Right pivot pin 3"
  circle A0 centre (26.6012, 28.0955) radius 2.5
extrude "Pin retainer''''''" add sketch "Pin retainer profile (7)" along normal blind 1 separate body makes body 37 in component "Right pivot pin 3"
ref_plane "WorkPlane1" through (0, 0, -6) normal (0, 0, 1) x (1, 0, 0) in component "Right pivot pin 4"
sketch "Pivot shaft profile (8)" plane through (0, 0, -6) normal (0, 0, 1) x (1, 0, 0) in component "Right pivot pin 4"
  circle A0 centre (26.6012, 50.0955) radius 1.5
extrude "Pivot shaft'''''''" add sketch "Pivot shaft profile (8)" along normal blind 12 separate body makes body 38 in component "Right pivot pin 4"
ref_plane "WorkPlane2" through (0, 0, 6) normal (0, 0, 1) x (1, 0, 0) in component "Right pivot pin 4"
sketch "Pin head profile (8)" plane through (0, 0, 6) normal (0, 0, 1) x (1, 0, 0) in component "Right pivot pin 4"
  circle A0 centre (26.6012, 50.0955) radius 2.5
extrude "Pin head'''''''" add sketch "Pin head profile (8)" along normal blind 1 separate body makes body 39 in component "Right pivot pin 4"
ref_plane "WorkPlane3" through (0, 0, -7) normal (0, 0, 1) x (1, 0, 0) in component "Right pivot pin 4"
sketch "Pin retainer profile (8)" plane through (0, 0, -7) normal (0, 0, 1) x (1, 0, 0) in component "Right pivot pin 4"
  circle A0 centre (26.6012, 50.0955) radius 2.5
extrude "Pin retainer'''''''" add sketch "Pin retainer profile (8)" along normal blind 1 separate body makes body 40 in component "Right pivot pin 4"
ref_plane "WorkPlane1" through (0, 0, 3) normal (0, 0, 1) x (1, 0, 0) in component "Servo pinion - 12T"
sketch "12 tooth pinion profile" plane through (0, 0, 3) normal (0, 0, 1) x (1, 0, 0) in component "Servo pinion - 12T"
  line L0 (5.3078, -14.4745) -> (6.3003, -14.3589)
  line L1 (6.3003, -14.3589) -> (6.548, -14.2803)
  line L2 (6.548, -14.2803) -> (6.7896, -14.1584)
  line L3 (6.7896, -14.1584) -> (7.0253, -14.0055)
  line L4 (7.0253, -14.0055) -> (7.2545, -13.8258)
  line L5 (7.2545, -13.8258) -> (7.4762, -13.6215)
  line L6 (7.4762, -13.6215) -> (7.6896, -13.394)
  line L7 (7.6896, -13.394) -> (7.5088, -12.7196)
  line L8 (7.5088, -12.7196) -> (7.2104, -12.6293)
  line L9 (7.2104, -12.6293) -> (6.9162, -12.5632)
  line L10 (6.9162, -12.5632) -> (6.6278, -12.5221)
  line L11 (6.6278, -12.5221) -> (6.3473, -12.5076)
  line L12 (6.3473, -12.5076) -> (6.0771, -12.5228)
  line L13 (6.0771, -12.5228) -> (5.8233, -12.5786)
  line L14 (5.8233, -12.5786) -> (4.906, -12.9747)
  line L15 (4.906, -12.9747) -> (4.2875, -11.9035)
  line L16 (4.2875, -11.9035) -> (5.0892, -11.3071)
  line L17 (5.0892, -11.3071) -> (5.2644, -11.1152)
  line L18 (5.2644, -11.1152) -> (5.4127, -10.8888)
  line L19 (5.4127, -10.8888) -> (5.5403, -10.6386)
  line L20 (5.5403, -10.6386) -> (5.6489, -10.3683)
  line L21 (5.6489, -10.3683) -> (5.7388, -10.0805)
  line L22 (5.7388, -10.0805) -> (5.8099, -9.7769)
  line L23 (5.8099, -9.7769) -> (5.3161, -9.2831)
  line L24 (5.3161, -9.2831) -> (5.0125, -9.3542)
  line L25 (5.0125, -9.3542) -> (4.7247, -9.4441)
  line L26 (4.7247, -9.4441) -> (4.4544, -9.5527)
  line L27 (4.4544, -9.5527) -> (4.2042, -9.6803)
  line L28 (4.2042, -9.6803) -> (3.9778, -9.8286)
  line L29 (3.9778, -9.8286) -> (3.7859, -10.0038)
  line L30 (3.7859, -10.0038) -> (3.1895, -10.8055)
  line L31 (3.1895, -10.8055) -> (2.1183, -10.187)
  line L32 (2.1183, -10.187) -> (2.5144, -9.2697)
  line L33 (2.5144, -9.2697) -> (2.5702, -9.0159)
  line L34 (2.5702, -9.0159) -> (2.5854, -8.7457)
  line L35 (2.5854, -8.7457) -> (2.5709, -8.4652)
  line L36 (2.5709, -8.4652) -> (2.5298, -8.1768)
  line L37 (2.5298, -8.1768) -> (2.4637, -7.8826)
  line L38 (2.4637, -7.8826) -> (2.3734, -7.5842)
  line L39 (2.3734, -7.5842) -> (1.699, -7.4034)
  line L40 (1.699, -7.4034) -> (1.4715, -7.6168)
  line L41 (1.4715, -7.6168) -> (1.2672, -7.8385)
  line L42 (1.2672, -7.8385) -> (1.0875, -8.0677)
  line L43 (1.0875, -8.0677) -> (0.9346, -8.3034)
  line L44 (0.9346, -8.3034) -> (0.8127, -8.545)
  line L45 (0.8127, -8.545) -> (0.7341, -8.7927)
  line L46 (0.7341, -8.7927) -> (0.6185, -9.7852)
  line L47 (0.6185, -9.7852) -> (-0.6185, -9.7852)
  line L48 (-0.6185, -9.7852) -> (-0.7341, -8.7927)
  line L49 (-0.7341, -8.7927) -> (-0.8127, -8.545)
  line L50 (-0.8127, -8.545) -> (-0.9346, -8.3034)
  line L51 (-0.9346, -8.3034) -> (-1.0875, -8.0677)
  line L52 (-1.0875, -8.0677) -> (-1.2672, -7.8385)
  line L53 (-1.2672, -7.8385) -> (-1.4715, -7.6168)
  line L54 (-1.4715, -7.6168) -> (-1.699, -7.4034)
  line L55 (-1.699, -7.4034) -> (-2.3734, -7.5842)
  line L56 (-2.3734, -7.5842) -> (-2.4637, -7.8826)
  line L57 (-2.4637, -7.8826) -> (-2.5298, -8.1768)
  line L58 (-2.5298, -8.1768) -> (-2.5709, -8.4652)
  line L59 (-2.5709, -8.4652) -> (-2.5854, -8.7457)
  line L60 (-2.5854, -8.7457) -> (-2.5702, -9.0159)
  line L61 (-2.5702, -9.0159) -> (-2.5144, -9.2697)
  line L62 (-2.5144, -9.2697) -> (-2.1183, -10.187)
  line L63 (-2.1183, -10.187) -> (-3.1895, -10.8055)
  line L64 (-3.1895, -10.8055) -> (-3.7859, -10.0038)
  line L65 (-3.7859, -10.0038) -> (-3.9778, -9.8286)
  line L66 (-3.9778, -9.8286) -> (-4.2042, -9.6803)
  line L67 (-4.2042, -9.6803) -> (-4.4544, -9.5527)
  line L68 (-4.4544, -9.5527) -> (-4.7247, -9.4441)
  line L69 (-4.7247, -9.4441) -> (-5.0125, -9.3542)
  line L70 (-5.0125, -9.3542) -> (-5.3161, -9.2831)
  line L71 (-5.3161, -9.2831) -> (-5.8099, -9.7769)
  line L72 (-5.8099, -9.7769) -> (-5.7388, -10.0805)
  line L73 (-5.7388, -10.0805) -> (-5.6489, -10.3683)
  line L74 (-5.6489, -10.3683) -> (-5.5403, -10.6386)
  line L75 (-5.5403, -10.6386) -> (-5.4127, -10.8888)
  line L76 (-5.4127, -10.8888) -> (-5.2644, -11.1152)
  line L77 (-5.2644, -11.1152) -> (-5.0892, -11.3071)
  line L78 (-5.0892, -11.3071) -> (-4.2875, -11.9035)
  line L79 (-4.2875, -11.9035) -> (-4.906, -12.9747)
  line L80 (-4.906, -12.9747) -> (-5.8233, -12.5786)
  line L81 (-5.8233, -12.5786) -> (-6.0771, -12.5228)
  line L82 (-6.0771, -12.5228) -> (-6.3473, -12.5076)
  line L83 (-6.3473, -12.5076) -> (-6.6278, -12.5221)
  line L84 (-6.6278, -12.5221) -> (-6.9162, -12.5632)
  line L85 (-6.9162, -12.5632) -> (-7.2104, -12.6293)
  line L86 (-7.2104, -12.6293) -> (-7.5088, -12.7196)
  line L87 (-7.5088, -12.7196) -> (-7.6896, -13.394)
  line L88 (-7.6896, -13.394) -> (-7.4762, -13.6215)
  line L89 (-7.4762, -13.6215) -> (-7.2545, -13.8258)
  line L90 (-7.2545, -13.8258) -> (-7.0253, -14.0055)
  line L91 (-7.0253, -14.0055) -> (-6.7896, -14.1584)
  line L92 (-6.7896, -14.1584) -> (-6.548, -14.2803)
  line L93 (-6.548, -14.2803) -> (-6.3003, -14.3589)
  line L94 (-6.3003, -14.3589) -> (-5.3078, -14.4745)
  line L95 (-5.3078, -14.4745) -> (-5.3078, -15.7115)
  line L96 (-5.3078, -15.7115) -> (-6.3003, -15.8271)
  line L97 (-6.3003, -15.8271) -> (-6.548, -15.9057)
  line L98 (-6.548, -15.9057) -> (-6.7896, -16.0276)
  line L99 (-6.7896, -16.0276) -> (-7.0253, -16.1805)
  line L100 (-7.0253, -16.1805) -> (-7.2545, -16.3602)
  line L101 (-7.2545, -16.3602) -> (-7.4762, -16.5645)
  line L102 (-7.4762, -16.5645) -> (-7.6896, -16.792)
  line L103 (-7.6896, -16.792) -> (-7.5088, -17.4664)
  line L104 (-7.5088, -17.4664) -> (-7.2104, -17.5567)
  line L105 (-7.2104, -17.5567) -> (-6.9162, -17.6228)
  line L106 (-6.9162, -17.6228) -> (-6.6278, -17.6639)
  line L107 (-6.6278, -17.6639) -> (-6.3473, -17.6784)
  line L108 (-6.3473, -17.6784) -> (-6.0771, -17.6632)
  line L109 (-6.0771, -17.6632) -> (-5.8233, -17.6074)
  line L110 (-5.8233, -17.6074) -> (-4.906, -17.2113)
  line L111 (-4.906, -17.2113) -> (-4.2875, -18.2825)
  line L112 (-4.2875, -18.2825) -> (-5.0892, -18.8789)
  line L113 (-5.0892, -18.8789) -> (-5.2644, -19.0708)
  line L114 (-5.2644, -19.0708) -> (-5.4127, -19.2972)
  line L115 (-5.4127, -19.2972) -> (-5.5403, -19.5474)
  line L116 (-5.5403, -19.5474) -> (-5.6489, -19.8177)
  line L117 (-5.6489, -19.8177) -> (-5.7388, -20.1055)
  line L118 (-5.7388, -20.1055) -> (-5.8099, -20.4091)
  line L119 (-5.8099, -20.4091) -> (-5.3161, -20.9029)
  line L120 (-5.3161, -20.9029) -> (-5.0125, -20.8318)
  line L121 (-5.0125, -20.8318) -> (-4.7247, -20.7419)
  line L122 (-4.7247, -20.7419) -> (-4.4544, -20.6333)
  line L123 (-4.4544, -20.6333) -> (-4.2042, -20.5057)
  line L124 (-4.2042, -20.5057) -> (-3.9778, -20.3574)
  line L125 (-3.9778, -20.3574) -> (-3.7859, -20.1822)
  line L126 (-3.7859, -20.1822) -> (-3.1895, -19.3805)
  line L127 (-3.1895, -19.3805) -> (-2.1183, -19.999)
  line L128 (-2.1183, -19.999) -> (-2.5144, -20.9163)
  line L129 (-2.5144, -20.9163) -> (-2.5702, -21.1701)
  line L130 (-2.5702, -21.1701) -> (-2.5854, -21.4403)
  line L131 (-2.5854, -21.4403) -> (-2.5709, -21.7208)
  line L132 (-2.5709, -21.7208) -> (-2.5298, -22.0092)
  line L133 (-2.5298, -22.0092) -> (-2.4637, -22.3034)
  line L134 (-2.4637, -22.3034) -> (-2.3734, -22.6018)
  line L135 (-2.3734, -22.6018) -> (-1.699, -22.7826)
  line L136 (-1.699, -22.7826) -> (-1.4715, -22.5692)
  line L137 (-1.4715, -22.5692) -> (-1.2672, -22.3475)
  line L138 (-1.2672, -22.3475) -> (-1.0875, -22.1183)
  line L139 (-1.0875, -22.1183) -> (-0.9346, -21.8826)
  line L140 (-0.9346, -21.8826) -> (-0.8127, -21.641)
  line L141 (-0.8127, -21.641) -> (-0.7341, -21.3933)
  line L142 (-0.7341, -21.3933) -> (-0.6185, -20.4008)
  line L143 (-0.6185, -20.4008) -> (0.6185, -20.4008)
  line L144 (0.6185, -20.4008) -> (0.7341, -21.3933)
  line L145 (0.7341, -21.3933) -> (0.8127, -21.641)
  line L146 (0.8127, -21.641) -> (0.9346, -21.8826)
  line L147 (0.9346, -21.8826) -> (1.0875, -22.1183)
  line L148 (1.0875, -22.1183) -> (1.2672, -22.3475)
  line L149 (1.2672, -22.3475) -> (1.4715, -22.5692)
  line L150 (1.4715, -22.5692) -> (1.699, -22.7826)
  line L151 (1.699, -22.7826) -> (2.3734, -22.6018)
  line L152 (2.3734, -22.6018) -> (2.4637, -22.3034)
  line L153 (2.4637, -22.3034) -> (2.5298, -22.0092)
  line L154 (2.5298, -22.0092) -> (2.5709, -21.7208)
  line L155 (2.5709, -21.7208) -> (2.5854, -21.4403)
  line L156 (2.5854, -21.4403) -> (2.5702, -21.1701)
  line L157 (2.5702, -21.1701) -> (2.5144, -20.9163)
  line L158 (2.5144, -20.9163) -> (2.1183, -19.999)
  line L159 (2.1183, -19.999) -> (3.1895, -19.3805)
  line L160 (3.1895, -19.3805) -> (3.7859, -20.1822)
  line L161 (3.7859, -20.1822) -> (3.9778, -20.3574)
  line L162 (3.9778, -20.3574) -> (4.2042, -20.5057)
  line L163 (4.2042, -20.5057) -> (4.4544, -20.6333)
  line L164 (4.4544, -20.6333) -> (4.7247, -20.7419)
  line L165 (4.7247, -20.7419) -> (5.0125, -20.8318)
  line L166 (5.0125, -20.8318) -> (5.3161, -20.9029)
  line L167 (5.3161, -20.9029) -> (5.8099, -20.4091)
  line L168 (5.8099, -20.4091) -> (5.7388, -20.1055)
  line L169 (5.7388, -20.1055) -> (5.6489, -19.8177)
  line L170 (5.6489, -19.8177) -> (5.5403, -19.5474)
  line L171 (5.5403, -19.5474) -> (5.4127, -19.2972)
  line L172 (5.4127, -19.2972) -> (5.2644, -19.0708)
  line L173 (5.2644, -19.0708) -> (5.0892, -18.8789)
  line L174 (5.0892, -18.8789) -> (4.2875, -18.2825)
  line L175 (4.2875, -18.2825) -> (4.906, -17.2113)
  line L176 (4.906, -17.2113) -> (5.8233, -17.6074)
  line L177 (5.8233, -17.6074) -> (6.0771, -17.6632)
  line L178 (6.0771, -17.6632) -> (6.3473, -17.6784)
  line L179 (6.3473, -17.6784) -> (6.6278, -17.6639)
  line L180 (6.6278, -17.6639) -> (6.9162, -17.6228)
  line L181 (6.9162, -17.6228) -> (7.2104, -17.5567)
  line L182 (7.2104, -17.5567) -> (7.5088, -17.4664)
  line L183 (7.5088, -17.4664) -> (7.6896, -16.792)
  line L184 (7.6896, -16.792) -> (7.4762, -16.5645)
  line L185 (7.4762, -16.5645) -> (7.2545, -16.3602)
  line L186 (7.2545, -16.3602) -> (7.0253, -16.1805)
  line L187 (7.0253, -16.1805) -> (6.7896, -16.0276)
  line L188 (6.7896, -16.0276) -> (6.548, -15.9057)
  line L189 (6.548, -15.9057) -> (6.3003, -15.8271)
  line L190 (6.3003, -15.8271) -> (5.3078, -15.7115)
  line L191 (5.3078, -15.7115) -> (5.3078, -14.4745)
extrude "12 tooth pinion" add sketch "12 tooth pinion profile" along normal blind 3 separate body makes body 41 in component "Servo pinion - 12T"
ref_plane "WorkPlane2" through (0, 0, -3) normal (0, 0, 1) x (1, 0, 0) in component "Servo pinion - 12T"
sketch "Shaft hub profile" plane through (0, 0, -3) normal (0, 0, 1) x (1, 0, 0) in component "Servo pinion - 12T"
  circle A0 centre (0, -15.093) radius 4
extrude "Shaft hub" add sketch "Shaft hub profile" along normal blind 6 separate body makes body 42 in component "Servo pinion - 12T"
ref_plane "WorkPlane3" through (0, 0, -3) normal (0, 0, 1) x (1, 0, 0) in component "Servo pinion - 12T"
sketch "Pivot holes (10)" plane through (0, 0, -3) normal (0, 0, 1) x (1, 0, 0) in component "Servo pinion - 12T"
  circle A0 centre (0, -15.093) radius 1.5
extrude "Through holes'''''''''" cut sketch "Pivot holes (10)" along normal blind 9 bodies 41 42 in component "Servo pinion - 12T"
sketch "Servo shaft rotation axis" plane through (0, 0, 0) normal (0, 0, 1) x (1, 0, 0) in component "Frame - twin 3 mm plates"
  point P0 (0, -15.093)
ref_plane "WorkPlane1" through (0, 0, -27) normal (0, 0, 1) x (1, 0, 0) in component "Servo motor - tutorial dimensions"
sketch "Servo case profile" plane through (0, 0, -27) normal (0, 0, 1) x (1, 0, 0) in component "Servo motor - tutorial dimensions"
  line L0 (-5.9, -20.993) -> (5.9, -20.993)
  line L1 (5.9, -20.993) -> (5.9, 1.507)
  line L2 (5.9, 1.507) -> (-5.9, 1.507)
  line L3 (-5.9, 1.507) -> (-5.9, -20.993)
extrude "Servo case" add sketch "Servo case profile" along normal blind 16.2 separate body makes body 43 in component "Servo motor - tutorial dimensions"
ref_plane "WorkPlane2" through (0, 0, -10.8) normal (0, 0, 1) x (1, 0, 0) in component "Servo motor - tutorial dimensions"
sketch "Mounting flange profile" plane through (0, 0, -10.8) normal (0, 0, 1) x (1, 0, 0) in component "Servo motor - tutorial dimensions"
  line L0 (-5.9, -20.993) -> (5.9, -20.993)
  line L1 (5.9, -20.993) -> (5.9, 11.007)
  line L2 (5.9, 11.007) -> (-5.9, 11.007)
  line L3 (-5.9, 11.007) -> (-5.9, -20.993)
extrude "Mounting flange" add sketch "Mounting flange profile" along normal blind 2.3 separate body makes body 44 in component "Servo motor - tutorial dimensions"
ref_plane "WorkPlane3" through (0, 0, -8.5) normal (0, 0, 1) x (1, 0, 0) in component "Servo motor - tutorial dimensions"
sketch "Upper case profile" plane through (0, 0, -8.5) normal (0, 0, 1) x (1, 0, 0) in component "Servo motor - tutorial dimensions"
  line L0 (-5.9, -20.993) -> (5.9, -20.993)
  line L1 (5.9, -20.993) -> (5.9, 1.507)
  line L2 (5.9, 1.507) -> (-5.9, 1.507)
  line L3 (-5.9, 1.507) -> (-5.9, -20.993)
extrude "Upper case" add sketch "Upper case profile" along normal blind 4.1 separate body makes body 45 in component "Servo motor - tutorial dimensions"
ref_plane "WorkPlane4" through (0, 0, -4.4) normal (0, 0, 1) x (1, 0, 0) in component "Servo motor - tutorial dimensions"